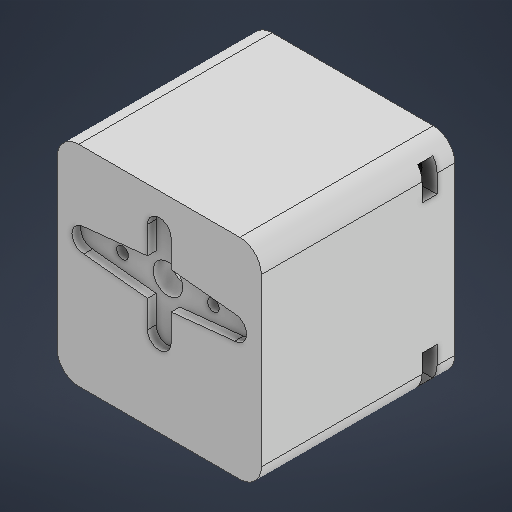
# Autodesk Inventor part: cajita
Saved by Autodesk Inventor 2027.2 (Build 312334000, 334)
## iProperties
Created: 2026-09-18
Part Number: cajita
Material: Genérico
Document SubType Name: Modeling
Designer: alexa
Density: 1 g/cm^3
Appearance: Valor por defecto
Project: Star tracker
Mass: 15.1395 g
Surface Area: 129.019 cm^2
Volume: 15.1395 cm^3
Author: alexa
Title: Porta camara
Autodesk Inventor part; units mm, degrees
sketch "Boceto1" plane through (0, 0, 0) normal (0, 0, 1) x (1, 0, 0)
  line L0 (17, 17.5) -> (17, -17.5) projected
  line L1 (-17, 17.5) -> (17, 17.5) projected
  line L2 (-17, -17.5) -> (-17, 17.5) projected
  line L3 (17, -17.5) -> (-17, -17.5) projected
  circle A0 centre (14.5, 15) radius 1.5 projected
  circle A1 centre (14.5, -15) radius 1.5 projected
  circle A2 centre (-14.5, -15) radius 1.5 projected
  circle A3 centre (-14.5, 15) radius 1.5 projected
  circle A4 centre (7.62, -9.69) radius 0.5 projected
  circle A5 centre (5.08, -12.23) radius 0.5 projected
  circle A6 centre (5.08, -9.69) radius 0.5 projected
  circle A7 centre (2.54, -12.23) radius 0.5 projected
  circle A8 centre (2.54, -9.69) radius 0.5 projected
  circle A9 centre (10, 4.5) radius 0.9 projected
  circle A10 centre (10.16, -12.23) radius 0.5 projected
  circle A11 centre (10.16, -9.69) radius 0.5 projected
  circle A12 centre (7.62, -12.23) radius 0.5 projected
  circle A13 centre (-5.08, -9.69) radius 0.5 projected
  circle A14 centre (-7.62, -12.23) radius 0.5 projected
  circle A15 centre (-7.62, -9.69) radius 0.5 projected
  circle A16 centre (-10.16, -12.23) radius 0.5 projected
  circle A17 centre (-10.16, -9.69) radius 0.5 projected
  circle A18 centre (-2.54, -12.23) radius 0.5 projected
  circle A19 centre (-2.54, -9.69) radius 0.5 projected
  circle A20 centre (-5.08, -12.23) radius 0.5 projected
  circle A21 centre (0, -9.69) radius 0.5 projected
  circle A22 centre (0, -12.23) radius 0.5 projected
  circle A23 centre (-10, 4.5) radius 0.9 projected
  line L4 (19, 19.5) -> (19, -19.5)
  line L5 (19, -19.5) -> (-19, -19.5)
  line L6 (-19, -19.5) -> (-19, 19.5)
  line L7 (-19, 19.5) -> (19, 19.5)
  circle A24 centre (-14.5, 15) radius 2.5
  circle A25 centre (14.5, 15) radius 2.5
  circle A26 centre (14.5, -15) radius 2.5
  circle A27 centre (-14.5, -15) radius 2.5
  line L8 (14.5, 12.5) -> (17, 12.5)
  line L9 (14.5, -12.5) -> (17, -12.5)
  line L10 (12, -15) -> (12, -17.5)
  line L11 (12, 15) -> (12, 17.5)
  line L12 (-12, 15) -> (-12, 17.5)
  line L13 (-14.5, 12.5) -> (-17, 12.5)
  line L14 (-14.5, -12.5) -> (-17, -12.5)
  line L15 (-12, -15) -> (-12, -17.5)
  point P0 (0, 0)
  dimension "d0" = 2
  constraints: 24 end point, 11 tangent, 10 point on line, 8 point on circle, 5 perpendicular, 4 centre point, 4 coincident, 1 horizontal, 1 parallel, 3 other
  measures "d0" distance between parallel lines of L1 L7
extrude "Extrusión1" add sketch "Boceto1" along normal blind 5 contours L0 A25 L1 | L0 L8 A25 | A25 | A25 L11 L1 | L0 A26 L9 | L12 A24 L1 | A26 | L0 L3 A26 | A24 L2 L1 | A24 | L3 L10 A26 | A24 L13 L2 | L3 A27 L15 | L14 A27 L2 | L3 L2 A27 | A27 | L4 L5 L6 L7
extrude "Extrusión2" add sketch "Boceto1" along normal blind 36 contours L4 L5 L6 L7
sketch "Boceto2" plane through (0, 0, 36) normal (0, 0, 1) x (1, 0, 0)
  line L0 (-19, 19.5) -> (-19, -19.5) projected
  line L1 (-19, -19.5) -> (19, -19.5) projected
  line L2 (19, -19.5) -> (19, 19.5) projected
  line L3 (19, 19.5) -> (-19, 19.5) projected
  line L4 (17, -17.5) -> (-17, -17.5) projected
  line L5 (-17, -17.5) -> (-17, 17.5) projected
  line L6 (-17, 17.5) -> (17, 17.5) projected
  line L7 (17, 17.5) -> (17, -17.5) projected
  circle A0 centre (0, 4.5) radius 10
  circle A1 centre (1.7663, -2.2735) radius 1.5
  circle A2 centre (6.7735, 6.2663) radius 1.5
  circle A3 centre (-1.7663, 11.2735) radius 1.5
  circle A4 centre (-6.7735, 2.7337) radius 1.5
  circle A5 centre (0, 4.5) radius 1.75
  point P0 (0, 0)
  constraints: 6 centre point
extrude "Extrusión3" add sketch "Boceto2" against normal blind 2 contours L4 L5 L6 L7 | A0 | A5
sketch "Boceto3" plane through (-19, -19.5, 0) normal (0, -1, 0) x (1, 0, 0)
  line L0 (0, 0) -> (38, 0) projected
  line L1 (38, 0) -> (38, 36) projected
  line L2 (0, 36) -> (38, 36) projected
  line L3 (0, 0) -> (0, 36) projected
  line L4 (7.57, 0) -> (7.57, 2.5) projected
  line L5 (30.43, 2.5) -> (30.43, 0) projected
  line L6 (7.57, 2.5) -> (7.57, 36)
  line L7 (30.43, 2.5) -> (30.43, 36)
  line L8 (7.57, 36) -> (7.57, 16)
  line L9 (7.57, 16) -> (30.43, 16)
  line L10 (7.57, 36) -> (7.57, 34)
  line L11 (7.57, 34) -> (30.6195, 34)
  point P0 (19, 0)
  point P1 (30.43, 34)
  dimension "d7" = 20
  dimension "d8" = 2
  constraints: 12 end point, 5 point on line, 3 perpendicular, 1 parallel
  measures "d7" distance of L6.end L8.end
  measures "d8" distance of L6.end L10.end
extrude "Extrusión4" cut sketch "Boceto3" against normal blind 2 contours L6 L11 L7 L9
fillet "Empalme1" radius 4 4 edges at (19, -19.5, 18) (-19, -19.5, 18) (-19, 19.5, 18) (19, 19.5, 18)
sketch "Boceto4" plane through (0, 0, 34) normal (0, 0, -1) x (-1, 0, 0)
  circle A0 centre (0, 4.5) radius 3.292
  point P0 (0, 0)
  constraints: 1 centre point
extrude "Extrusión5" cut sketch "Boceto4" against normal blind 2
ref_plane "Plano de trabajo1" through (0, 0, 31) normal (0, 0, 1) x (1, 0, 0)
sketch "Reforzar_pared_trasera_a_5_mm_perfil" plane through (0, 0, 31) normal (0, 0, 1) x (1, 0, 0)
  line L0 (-19, -19.5) -> (19, -19.5)
  line L1 (19, -19.5) -> (19, 19.5)
  line L2 (19, 19.5) -> (-19, 19.5)
  line L3 (-19, 19.5) -> (-19, -19.5)
  constraints: 8 end point
extrude "Reforzar_pared_trasera_a_5_mm" add sketch "Reforzar_pared_trasera_a_5_mm_perfil" along normal blind 5
ref_plane "Plano de trabajo2" through (0, 0, 34.38) normal (0, 0, 1) x (1, 0, 0)
sketch "Huella_cruz_roll_centro_perfil" plane through (0, 0, 34.38) normal (0, 0, 1) x (1, 0, 0)
  circle A0 centre (0, 4.5) radius 3.65
  constraints: 1 centre point
extrude "Huella_cruz_roll_centro" cut sketch "Huella_cruz_roll_centro_perfil" along normal blind 1.64
ref_plane "Plano de trabajo3" through (0, 0, 34.38) normal (0, 0, 1) x (1, 0, 0)
sketch "Huella_cruz_roll_ala_larga_-1_perfil" plane through (0, 0, 34.38) normal (0, 0, 1) x (1, 0, 0)
  line L0 (0, 0.85) -> (0, 8.15)
  line L1 (0, 8.15) -> (-14.05, 6.7)
  line L2 (-14.05, 6.7) -> (-14.05, 2.3)
  line L3 (-14.05, 2.3) -> (0, 0.85)
  constraints: 8 end point
extrude "Huella_cruz_roll_ala_larga_-1" cut sketch "Huella_cruz_roll_ala_larga_-1_perfil" along normal blind 1.64
ref_plane "Plano de trabajo4" through (0, 0, 34.38) normal (0, 0, 1) x (1, 0, 0)
sketch "Huella_cruz_roll_punta_larga_-1_perfil" plane through (0, 0, 34.38) normal (0, 0, 1) x (1, 0, 0)
  circle A0 centre (-14.05, 4.5) radius 2.2
  constraints: 1 centre point
extrude "Huella_cruz_roll_punta_larga_-1" cut sketch "Huella_cruz_roll_punta_larga_-1_perfil" along normal blind 1.64
ref_plane "Plano de trabajo5" through (0, 0, 34.38) normal (0, 0, 1) x (1, 0, 0)
sketch "Huella_cruz_roll_ala_larga_1_perfil" plane through (0, 0, 34.38) normal (0, 0, 1) x (1, 0, 0)
  line L0 (0, 0.85) -> (0, 8.15)
  line L1 (0, 8.15) -> (14.05, 6.7)
  line L2 (14.05, 6.7) -> (14.05, 2.3)
  line L3 (14.05, 2.3) -> (0, 0.85)
  constraints: 8 end point
extrude "Huella_cruz_roll_ala_larga_1" cut sketch "Huella_cruz_roll_ala_larga_1_perfil" along normal blind 1.64
ref_plane "Plano de trabajo6" through (0, 0, 34.38) normal (0, 0, 1) x (1, 0, 0)
sketch "Huella_cruz_roll_punta_larga_1_perfil" plane through (0, 0, 34.38) normal (0, 0, 1) x (1, 0, 0)
  circle A0 centre (14.05, 4.5) radius 2.2
  constraints: 1 centre point
extrude "Huella_cruz_roll_punta_larga_1" cut sketch "Huella_cruz_roll_punta_larga_1_perfil" along normal blind 1.64
ref_plane "Plano de trabajo7" through (0, 0, 34.38) normal (0, 0, 1) x (1, 0, 0)
sketch "Huella_cruz_roll_alas_cortas_perfil" plane through (0, 0, 34.38) normal (0, 0, 1) x (1, 0, 0)
  line L0 (-2.2, -4) -> (2.2, -4)
  line L1 (2.2, -4) -> (2.2, 13)
  line L2 (2.2, 13) -> (-2.2, 13)
  line L3 (-2.2, 13) -> (-2.2, -4)
  constraints: 8 end point
extrude "Huella_cruz_roll_alas_cortas" cut sketch "Huella_cruz_roll_alas_cortas_perfil" along normal blind 1.64
ref_plane "Plano de trabajo8" through (0, 0, 34.38) normal (0, 0, 1) x (1, 0, 0)
sketch "Huella_cruz_roll_punta_corta_-1_perfil" plane through (0, 0, 34.38) normal (0, 0, 1) x (1, 0, 0)
  circle A0 centre (0, -4) radius 2.2
  constraints: 1 centre point
extrude "Huella_cruz_roll_punta_corta_-1" cut sketch "Huella_cruz_roll_punta_corta_-1_perfil" along normal blind 1.64
ref_plane "Plano de trabajo9" through (0, 0, 34.38) normal (0, 0, 1) x (1, 0, 0)
sketch "Huella_cruz_roll_punta_corta_1_perfil" plane through (0, 0, 34.38) normal (0, 0, 1) x (1, 0, 0)
  circle A0 centre (0, 13) radius 2.2
  constraints: 1 centre point
extrude "Huella_cruz_roll_punta_corta_1" cut sketch "Huella_cruz_roll_punta_corta_1_perfil" along normal blind 1.64
ref_plane "Plano de trabajo10" through (0, 0, 30.9) normal (0, 0, 1) x (1, 0, 0)
sketch "Acople_roll_acceso_central_perfil" plane through (0, 0, 30.9) normal (0, 0, 1) x (1, 0, 0)
  circle A0 centre (0, 4.5) radius 2.75
  constraints: 1 centre point
extrude "Acople_roll_acceso_central" cut sketch "Acople_roll_acceso_central_perfil" along normal blind 5.2
ref_plane "Plano de trabajo11" through (0, 0, 30.9) normal (0, 0, 1) x (1, 0, 0)
sketch "Acople_roll_paso_M2_-1_perfil" plane through (0, 0, 30.9) normal (0, 0, 1) x (1, 0, 0)
  circle A0 centre (-8.45, 4.5) radius 1.1
  constraints: 1 centre point
extrude "Acople_roll_paso_M2_-1" cut sketch "Acople_roll_paso_M2_-1_perfil" along normal blind 5.2
ref_plane "Plano de trabajo12" through (0, 0, 30.98) normal (0, 0, 1) x (1, 0, 0)
sketch "Acople_roll_tuerca_M2_-1_perfil" plane through (0, 0, 30.98) normal (0, 0, 1) x (1, 0, 0)
  line L0 (-6.0251, 4.5) -> (-7.2376, 6.6)
  line L1 (-7.2376, 6.6) -> (-9.6624, 6.6)
  line L2 (-9.6624, 6.6) -> (-10.8749, 4.5)
  line L3 (-10.8749, 4.5) -> (-9.6624, 2.4)
  line L4 (-9.6624, 2.4) -> (-7.2376, 2.4)
  line L5 (-7.2376, 2.4) -> (-6.0251, 4.5)
  constraints: 12 end point
extrude "Acople_roll_tuerca_M2_-1" cut sketch "Acople_roll_tuerca_M2_-1_perfil" along normal blind 1.84
ref_plane "Plano de trabajo13" through (0, 0, 30.9) normal (0, 0, 1) x (1, 0, 0)
sketch "Acople_roll_paso_M2_1_perfil" plane through (0, 0, 30.9) normal (0, 0, 1) x (1, 0, 0)
  circle A0 centre (8.45, 4.5) radius 1.1
  constraints: 1 centre point
extrude "Acople_roll_paso_M2_1" cut sketch "Acople_roll_paso_M2_1_perfil" along normal blind 5.2
ref_plane "Plano de trabajo14" through (0, 0, 30.98) normal (0, 0, 1) x (1, 0, 0)
sketch "Acople_roll_tuerca_M2_1_perfil" plane through (0, 0, 30.98) normal (0, 0, 1) x (1, 0, 0)
  line L0 (10.8749, 4.5) -> (9.6624, 6.6)
  line L1 (9.6624, 6.6) -> (7.2376, 6.6)
  line L2 (7.2376, 6.6) -> (6.0251, 4.5)
  line L3 (6.0251, 4.5) -> (7.2376, 2.4)
  line L4 (7.2376, 2.4) -> (9.6624, 2.4)
  line L5 (9.6624, 2.4) -> (10.8749, 4.5)
  constraints: 12 end point
extrude "Acople_roll_tuerca_M2_1" cut sketch "Acople_roll_tuerca_M2_1_perfil" along normal blind 1.84
ref_plane "Plano de trabajo15" through (0, 0, 2) normal (0, 0, 1) x (1, 0, 0)
sketch "Apoyo_tuerca_M3_-14.5_-15_perfil" plane through (0, 0, 2) normal (0, 0, 1) x (1, 0, 0)
  circle A0 centre (-14.5, -15) radius 4.5
  constraints: 1 centre point
extrude "Apoyo_tuerca_M3_-14.5_-15" add sketch "Apoyo_tuerca_M3_-14.5_-15_perfil" along normal blind 4
ref_plane "Plano de trabajo16" through (0, 0, -0.1) normal (0, 0, 1) x (1, 0, 0)
sketch "Paso_camara_M3_-14.5_-15_perfil" plane through (0, 0, -0.1) normal (0, 0, 1) x (1, 0, 0)
  circle A0 centre (-14.5, -15) radius 1.7
  constraints: 1 centre point
extrude "Paso_camara_M3_-14.5_-15" cut sketch "Paso_camara_M3_-14.5_-15_perfil" along normal blind 6.2
ref_plane "Plano de trabajo17" through (0, 0, 3.3) normal (0, 0, 1) x (1, 0, 0)
sketch "Tuerca_camara_M3_-14.5_-15_perfil" plane through (0, 0, 3.3) normal (0, 0, 1) x (1, 0, 0)
  line L0 (-11.1514, -15) -> (-12.8257, -12.1)
  line L1 (-12.8257, -12.1) -> (-16.1743, -12.1)
  line L2 (-16.1743, -12.1) -> (-17.8486, -15)
  line L3 (-17.8486, -15) -> (-16.1743, -17.9)
  line L4 (-16.1743, -17.9) -> (-12.8257, -17.9)
  line L5 (-12.8257, -17.9) -> (-11.1514, -15)
  constraints: 12 end point
extrude "Tuerca_camara_M3_-14.5_-15" cut sketch "Tuerca_camara_M3_-14.5_-15_perfil" along normal blind 2.8
ref_plane "Plano de trabajo18" through (0, 0, 3.3) normal (0, 0, 1) x (1, 0, 0)
sketch "Entrada_lateral_M3_-14.5_-15_perfil" plane through (0, 0, 3.3) normal (0, 0, 1) x (1, 0, 0)
  line L0 (-19.1, -17.9) -> (-14.5, -17.9)
  line L1 (-14.5, -17.9) -> (-14.5, -12.1)
  line L2 (-14.5, -12.1) -> (-19.1, -12.1)
  line L3 (-19.1, -12.1) -> (-19.1, -17.9)
  constraints: 8 end point
extrude "Entrada_lateral_M3_-14.5_-15" cut sketch "Entrada_lateral_M3_-14.5_-15_perfil" along normal blind 2.8
ref_plane "Plano de trabajo19" through (0, 0, 2) normal (0, 0, 1) x (1, 0, 0)
sketch "Apoyo_tuerca_M3_-14.5_15_perfil" plane through (0, 0, 2) normal (0, 0, 1) x (1, 0, 0)
  circle A0 centre (-14.5, 15) radius 4.5
  constraints: 1 centre point
extrude "Apoyo_tuerca_M3_-14.5_15" add sketch "Apoyo_tuerca_M3_-14.5_15_perfil" along normal blind 4
ref_plane "Plano de trabajo20" through (0, 0, -0.1) normal (0, 0, 1) x (1, 0, 0)
sketch "Paso_camara_M3_-14.5_15_perfil" plane through (0, 0, -0.1) normal (0, 0, 1) x (1, 0, 0)
  circle A0 centre (-14.5, 15) radius 1.7
  constraints: 1 centre point
extrude "Paso_camara_M3_-14.5_15" cut sketch "Paso_camara_M3_-14.5_15_perfil" along normal blind 6.2
ref_plane "Plano de trabajo21" through (0, 0, 3.3) normal (0, 0, 1) x (1, 0, 0)
sketch "Tuerca_camara_M3_-14.5_15_perfil" plane through (0, 0, 3.3) normal (0, 0, 1) x (1, 0, 0)
  line L0 (-11.1514, 15) -> (-12.8257, 17.9)
  line L1 (-12.8257, 17.9) -> (-16.1743, 17.9)
  line L2 (-16.1743, 17.9) -> (-17.8486, 15)
  line L3 (-17.8486, 15) -> (-16.1743, 12.1)
  line L4 (-16.1743, 12.1) -> (-12.8257, 12.1)
  line L5 (-12.8257, 12.1) -> (-11.1514, 15)
  constraints: 12 end point
extrude "Tuerca_camara_M3_-14.5_15" cut sketch "Tuerca_camara_M3_-14.5_15_perfil" along normal blind 2.8
ref_plane "Plano de trabajo22" through (0, 0, 3.3) normal (0, 0, 1) x (1, 0, 0)
sketch "Entrada_lateral_M3_-14.5_15_perfil" plane through (0, 0, 3.3) normal (0, 0, 1) x (1, 0, 0)
  line L0 (-19.1, 12.1) -> (-14.5, 12.1)
  line L1 (-14.5, 12.1) -> (-14.5, 17.9)
  line L2 (-14.5, 17.9) -> (-19.1, 17.9)
  line L3 (-19.1, 17.9) -> (-19.1, 12.1)
  constraints: 8 end point
extrude "Entrada_lateral_M3_-14.5_15" cut sketch "Entrada_lateral_M3_-14.5_15_perfil" along normal blind 2.8
ref_plane "Plano de trabajo23" through (0, 0, 2) normal (0, 0, 1) x (1, 0, 0)
sketch "Apoyo_tuerca_M3_14.5_-15_perfil" plane through (0, 0, 2) normal (0, 0, 1) x (1, 0, 0)
  circle A0 centre (14.5, -15) radius 4.5
  constraints: 1 centre point
extrude "Apoyo_tuerca_M3_14.5_-15" add sketch "Apoyo_tuerca_M3_14.5_-15_perfil" along normal blind 4
ref_plane "Plano de trabajo24" through (0, 0, -0.1) normal (0, 0, 1) x (1, 0, 0)
sketch "Paso_camara_M3_14.5_-15_perfil" plane through (0, 0, -0.1) normal (0, 0, 1) x (1, 0, 0)
  circle A0 centre (14.5, -15) radius 1.7
  constraints: 1 centre point
extrude "Paso_camara_M3_14.5_-15" cut sketch "Paso_camara_M3_14.5_-15_perfil" along normal blind 6.2
ref_plane "Plano de trabajo25" through (0, 0, 3.3) normal (0, 0, 1) x (1, 0, 0)
sketch "Tuerca_camara_M3_14.5_-15_perfil" plane through (0, 0, 3.3) normal (0, 0, 1) x (1, 0, 0)
  line L0 (17.8486, -15) -> (16.1743, -12.1)
  line L1 (16.1743, -12.1) -> (12.8257, -12.1)
  line L2 (12.8257, -12.1) -> (11.1514, -15)
  line L3 (11.1514, -15) -> (12.8257, -17.9)
  line L4 (12.8257, -17.9) -> (16.1743, -17.9)
  line L5 (16.1743, -17.9) -> (17.8486, -15)
  constraints: 12 end point
extrude "Tuerca_camara_M3_14.5_-15" cut sketch "Tuerca_camara_M3_14.5_-15_perfil" along normal blind 2.8
ref_plane "Plano de trabajo26" through (0, 0, 3.3) normal (0, 0, 1) x (1, 0, 0)
sketch "Entrada_lateral_M3_14.5_-15_perfil" plane through (0, 0, 3.3) normal (0, 0, 1) x (1, 0, 0)
  line L0 (14.5, -17.9) -> (19.1, -17.9)
  line L1 (19.1, -17.9) -> (19.1, -12.1)
  line L2 (19.1, -12.1) -> (14.5, -12.1)
  line L3 (14.5, -12.1) -> (14.5, -17.9)
  constraints: 8 end point
extrude "Entrada_lateral_M3_14.5_-15" cut sketch "Entrada_lateral_M3_14.5_-15_perfil" along normal blind 2.8
ref_plane "Plano de trabajo27" through (0, 0, 2) normal (0, 0, 1) x (1, 0, 0)
sketch "Apoyo_tuerca_M3_14.5_15_perfil" plane through (0, 0, 2) normal (0, 0, 1) x (1, 0, 0)
  circle A0 centre (14.5, 15) radius 4.5
  constraints: 1 centre point
extrude "Apoyo_tuerca_M3_14.5_15" add sketch "Apoyo_tuerca_M3_14.5_15_perfil" along normal blind 4
ref_plane "Plano de trabajo28" through (0, 0, -0.1) normal (0, 0, 1) x (1, 0, 0)
sketch "Paso_camara_M3_14.5_15_perfil" plane through (0, 0, -0.1) normal (0, 0, 1) x (1, 0, 0)
  circle A0 centre (14.5, 15) radius 1.7
  constraints: 1 centre point
extrude "Paso_camara_M3_14.5_15" cut sketch "Paso_camara_M3_14.5_15_perfil" along normal blind 6.2
ref_plane "Plano de trabajo29" through (0, 0, 3.3) normal (0, 0, 1) x (1, 0, 0)
sketch "Tuerca_camara_M3_14.5_15_perfil" plane through (0, 0, 3.3) normal (0, 0, 1) x (1, 0, 0)
  line L0 (17.8486, 15) -> (16.1743, 17.9)
  line L1 (16.1743, 17.9) -> (12.8257, 17.9)
  line L2 (12.8257, 17.9) -> (11.1514, 15)
  line L3 (11.1514, 15) -> (12.8257, 12.1)
  line L4 (12.8257, 12.1) -> (16.1743, 12.1)
  line L5 (16.1743, 12.1) -> (17.8486, 15)
  constraints: 12 end point
extrude "Tuerca_camara_M3_14.5_15" cut sketch "Tuerca_camara_M3_14.5_15_perfil" along normal blind 2.8
ref_plane "Plano de trabajo30" through (0, 0, 3.3) normal (0, 0, 1) x (1, 0, 0)
sketch "Entrada_lateral_M3_14.5_15_perfil" plane through (0, 0, 3.3) normal (0, 0, 1) x (1, 0, 0)
  line L0 (14.5, 12.1) -> (19.1, 12.1)
  line L1 (19.1, 12.1) -> (19.1, 17.9)
  line L2 (19.1, 17.9) -> (14.5, 17.9)
  line L3 (14.5, 17.9) -> (14.5, 12.1)
  constraints: 8 end point
extrude "Entrada_lateral_M3_14.5_15" cut sketch "Entrada_lateral_M3_14.5_15_perfil" along normal blind 2.8
ref_plane "Plano de trabajo31" through (0, 0, 1.9) normal (0, 0, 1) x (1, 0, 0)
sketch "Holgura_conector_trasero_OV7670_perfil" plane through (0, 0, 1.9) normal (0, 0, 1) x (1, 0, 0)
  line L0 (-11.7, -13.8) -> (11.7, -13.8)
  line L1 (11.7, -13.8) -> (11.7, -11.4)
  line L2 (11.7, -11.4) -> (-11.7, -11.4)
  line L3 (-11.7, -11.4) -> (-11.7, -13.8)
  constraints: 8 end point
extrude "Holgura_conector_trasero_OV7670" cut sketch "Holgura_conector_trasero_OV7670_perfil" along normal blind 0.9
ref_plane "Roll_plano_axial" through (0, 4.5, -1.5) normal (0, 0, -1) x (-1, 0, 0)
ref_plane "Roll_cero" through (0, 4.5, -1.5) normal (-1, 0, 0) x (0, 0, -1)
ref_plane "Cruz_roll_ref_1" through (0, 4.5, 34.4) normal (-1, 0, 0) x (0, 1, 0)
ref_plane "Cruz_roll_ref_2" through (0, 4.5, 34.4) normal (0, 1, 0) x (1, 0, 0)
ref_plane "Cruz_roll_ref_3" through (0, 4.5, 34.4) normal (0, 0, -1) x (1, 0, 0)
ref_plane "OV7670_ref_1" through (0, 0, 0) normal (-1, 0, 0) x (0, 1, 0)
ref_plane "OV7670_ref_2" through (0, 0, 0) normal (0, 1, 0) x (1, 0, 0)
ref_plane "OV7670_ref_3" through (0, 0, 0) normal (0, 0, -1) x (1, 0, 0)
ref_plane "M2_cruz_roll_0_ref_1" through (-8.45, 4.5, 31.1) normal (1, 0, 0) x (0, 1, 0)
ref_plane "M2_cruz_roll_0_ref_2" through (-8.45, 4.5, 31.1) normal (0, 1, 0) x (1, 0, 0)
ref_plane "M2_cruz_roll_0_ref_3" through (-8.45, 4.5, 31.1) normal (0, 0, 1) x (1, 0, 0)
ref_plane "M2_cruz_roll_1_ref_1" through (8.45, 4.5, 31.1) normal (1, 0, 0) x (0, 1, 0)
ref_plane "M2_cruz_roll_1_ref_2" through (8.45, 4.5, 31.1) normal (0, 1, 0) x (1, 0, 0)
ref_plane "M2_cruz_roll_1_ref_3" through (8.45, 4.5, 31.1) normal (0, 0, 1) x (1, 0, 0)
ref_plane "M3_camara_0_ref_1" through (-14.5, -15, 3.4) normal (1, 0, 0) x (0, 1, 0)
ref_plane "M3_camara_0_ref_2" through (-14.5, -15, 3.4) normal (0, 1, 0) x (1, 0, 0)
ref_plane "M3_camara_0_ref_3" through (-14.5, -15, 3.4) normal (0, 0, 1) x (1, 0, 0)
ref_plane "M3_camara_1_ref_1" through (-14.5, 15, 3.4) normal (1, 0, 0) x (0, 1, 0)
ref_plane "M3_camara_1_ref_2" through (-14.5, 15, 3.4) normal (0, 1, 0) x (1, 0, 0)
ref_plane "M3_camara_1_ref_3" through (-14.5, 15, 3.4) normal (0, 0, 1) x (1, 0, 0)
ref_plane "M3_camara_2_ref_1" through (14.5, -15, 3.4) normal (1, 0, 0) x (0, 1, 0)
ref_plane "M3_camara_2_ref_2" through (14.5, -15, 3.4) normal (0, 1, 0) x (1, 0, 0)
ref_plane "M3_camara_2_ref_3" through (14.5, -15, 3.4) normal (0, 0, 1) x (1, 0, 0)
ref_plane "M3_camara_3_ref_1" through (14.5, 15, 3.4) normal (1, 0, 0) x (0, 1, 0)
ref_plane "M3_camara_3_ref_2" through (14.5, 15, 3.4) normal (0, 1, 0) x (1, 0, 0)
ref_plane "M3_camara_3_ref_3" through (14.5, 15, 3.4) normal (0, 0, 1) x (1, 0, 0)
sketch "Boceto36" plane through (0, 0, 31) normal (0, 0, -1) x (-1, 0, 0)
  circle A0 centre (-14.5, 15) radius 1.7 projected
  circle A1 centre (-14.5, -15) radius 1.7 projected
  circle A2 centre (14.5, 15) radius 1.7 projected
  circle A3 centre (14.5, -15) radius 1.7 projected
  arc A4 (-15, 19.5) -> (-19, 15.5) centre (-15, 15.5) ccw projected
  line L0 (-19, -15.5) -> (-19, 15.5) projected
  arc A5 (-19, -15.5) -> (-15, -19.5) centre (-15, -15.5) ccw projected
  line L1 (15, -19.5) -> (-15, -19.5) projected
  arc A6 (15, -19.5) -> (19, -15.5) centre (15, -15.5) ccw projected
  line L2 (19, 15.5) -> (19, -15.5) projected
  arc A7 (19, 15.5) -> (15, 19.5) centre (15, 15.5) ccw projected
  line L3 (-15, 19.5) -> (15, 19.5) projected
  line L4 (12, 15) -> (12, 17.5) projected
  arc A8 (12, 15) -> (14.5, 12.5) centre (14.5, 15) ccw projected
  line L5 (17, 12.5) -> (14.5, 12.5) projected
  line L6 (17, -12.5) -> (17, 12.5) projected
  line L7 (14.5, -12.5) -> (17, -12.5) projected
  arc A9 (14.5, -12.5) -> (12, -15) centre (14.5, -15) ccw projected
  line L8 (12, -17.5) -> (12, -15) projected
  line L9 (-12, -17.5) -> (12, -17.5) projected
  line L10 (-12, -15) -> (-12, -17.5) projected
  arc A10 (-12, -15) -> (-14.5, -12.5) centre (-14.5, -15) ccw projected
  line L11 (-17, -12.5) -> (-14.5, -12.5) projected
  line L12 (-17, 12.5) -> (-17, -12.5) projected
  line L13 (-14.5, 12.5) -> (-17, 12.5) projected
  arc A11 (-14.5, 12.5) -> (-12, 15) centre (-14.5, 15) ccw projected
  line L14 (-12, 17.5) -> (-12, 15) projected
  line L15 (12, 17.5) -> (-12, 17.5) projected
  line L16 (-15, -19.5) -> (-19, -19.5) projected
  line L17 (-19, -19.5) -> (-19, -15.5) projected
  line L18 (-19, 15.5) -> (-19, 19.5) projected
  line L19 (-19, 19.5) -> (-15, 19.5) projected
  line L20 (15, 19.5) -> (19, 19.5) projected
  line L21 (19, 19.5) -> (19, 15.5) projected
  line L22 (19, -15.5) -> (19, -19.5) projected
  line L23 (19, -19.5) -> (15, -19.5) projected
  point P0 (0, 0)
extrude "Extrusión37" cut sketch "Boceto36" against normal blind 10 contours A4 L18 L19 | L20 L21 A7 | A5 L16 L17 | L22 L23 A6
